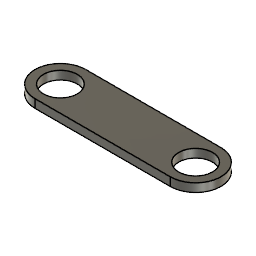
Connecting_Rod (Autodesk Fusion 360 design; units mm, degrees)
Autodesk Fusion 360 part; units mm, degrees
sketch "Sketch1" plane through (0, 0, 0) normal (0, 0, 1) x (1, 0, 0)
  circle A0 centre (0, 0) radius 10
  circle A1 centre (80, 0) radius 10
  line L0 (0, 15) -> (80, 15)
  line L1 (80, -15) -> (0, -15)
  line L2 (0, 0) -> (10, 0) construction
  line L3 (70, 0) -> (80, 0) construction
  arc A2 (0, 15) -> (0, -15) centre (0, 0) ccw
  arc A3 (80, -15) -> (80, 15) centre (80, 0) ccw
  dimension "d1" = 20
  dimension "d3" = 80
  constraint coincident A0.centre L2.start
  constraint horizontal L2
  constraint coincident A1.centre L3.end
  constraint tangent L0 A3
  constraint horizontal L0
  constraint tangent L1 A2
  constraint parallel L0 L1
  constraint collinear L2 L3
  constraint concentric A0 A2
  constraint coincident A0 L2.end
  constraint concentric A1 A3
  constraint coincident A1 L3.start
  measures "d1" diameter of A0
  measures "d3" distance of A0.centre A1.centre
extrude "Extrude2" add sketch "Sketch1" along normal blind 5
extrude "Extrude1" [suppressed]
